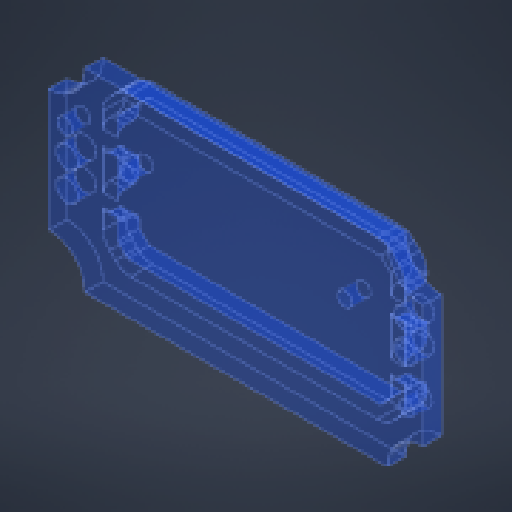
# Autodesk Inventor part: MID_PLATE
Saved by Autodesk Inventor 2024.3 (Build 283343000, 343)
## iProperties
Created: 2026-06-30
Part Number: MID_PLATE
Material: Generic
Document SubType Name: Modeling
Designer: REMOTE
Density: 1 g/cm^3
Appearance: Clear - Blue
Author: REMOTE
Autodesk Inventor part; units mm, degrees
ref_plane "YZ Plane" through (0, 0, 0) normal (1, 0, 0) x (0, 1, 0)
ref_plane "XZ Plane" through (0, 0, 0) normal (0, 1, 0) x (-1, 0, 0)
ref_plane "XY Plane" through (0, 0, 0) normal (0, 0, 1) x (1, 0, 0)
sketch "Sketch1" plane through (0, 0, 0) normal (0, 0, 1) x (1, 0, 0)
  line L0 (-71.4252, 28.7769) -> (-71.4252, -3.5231)
  line L1 (-71.4252, -3.5231) -> (-14.1252, -3.5231)
  line L2 (-14.1252, -3.5231) -> (-14.1252, 28.7769)
  line L3 (-14.1252, 28.7769) -> (-71.4252, 28.7769)
  line L4 (-16.6252, -1.0231) -> (-68.9252, -1.0231)
  line L5 (-68.9252, -1.0231) -> (-68.9252, 26.2769)
  line L6 (-68.9252, 26.2769) -> (-16.6252, 26.2769)
  line L7 (-16.6252, 26.2769) -> (-16.6252, -1.0231)
  line L8 (-16.6252, 0.2269) -> (-68.9252, 0.2269)
  line L9 (-68.9252, 25.0269) -> (-16.6252, 25.0269)
  line L10 (-68.7252, 26.0769) -> (-68.7252, -0.8231)
  line L11 (-68.7252, -0.8231) -> (-16.8252, -0.8231)
  line L12 (-16.8252, -0.8231) -> (-16.8252, 26.0769)
  line L13 (-16.8252, 26.0769) -> (-68.7252, 26.0769)
  point P0 (0, 0)
  point P1 (-42.7752, 12.6269)
  dimension "d0" = 0.2
  constraints: 28 end point, 3 other
  measures "d0" distance between parallel lines of L5 L10
extrude "Extrusion1" add sketch "Sketch1" along normal blind 2.5 contours L12 L11 L10 L8 | L8 L10 L9 L12 | L9 L10 L13 L12
sketch "Sketch2" plane through (0, 0, 0) normal (0, 0, -1) x (-1, 0, 0)
  line L0 (25.3752, 21.2419) -> (24.1752, 20.0419) projected
  line L1 (24.1752, 20.0419) -> (24.1752, 5.2119) projected
  line L2 (24.1752, 5.2119) -> (25.3752, 4.0119) projected
  line L3 (25.3752, 4.0119) -> (60.1752, 4.0119) projected
  line L4 (60.1752, 4.0119) -> (61.3752, 5.2119) projected
  line L5 (61.3752, 5.2119) -> (61.3752, 20.0419) projected
  line L6 (61.3752, 20.0419) -> (60.1752, 21.2419) projected
  line L7 (60.1752, 21.2419) -> (25.3752, 21.2419) projected
  circle A0 centre (57.8752, 16.3919) radius 1 projected
  circle A1 centre (27.6752, 8.9719) radius 1 projected
  circle A2 centre (57.8752, 8.9719) radius 1 projected
  circle A3 centre (27.6752, 16.3919) radius 1 projected
  line L8 (61.6752, 20.1662) -> (61.6752, 5.0876)
  line L9 (61.6752, 5.0876) -> (60.2994, 3.7119)
  line L10 (60.2994, 3.7119) -> (25.2509, 3.7119)
  line L11 (25.2509, 3.7119) -> (23.8752, 5.0876)
  line L12 (23.8752, 5.0876) -> (23.8752, 20.1662)
  line L13 (23.8752, 20.1662) -> (25.2509, 21.5419)
  line L14 (25.2509, 21.5419) -> (60.2994, 21.5419)
  line L15 (60.2994, 21.5419) -> (61.6752, 20.1662)
  line L16 (63.6752, 4.2592) -> (63.6752, 20.9946)
  line L17 (63.6752, 20.9946) -> (61.1279, 23.5419)
  line L18 (61.1279, 23.5419) -> (24.4225, 23.5419)
  line L19 (24.4225, 23.5419) -> (21.8752, 20.9946)
  line L20 (21.8752, 20.9946) -> (21.8752, 4.2592)
  line L21 (21.8752, 4.2592) -> (24.4225, 1.7119)
  line L22 (24.4225, 1.7119) -> (61.1279, 1.7119)
  line L23 (61.1279, 1.7119) -> (63.6752, 4.2592)
  point P0 (0, 0)
  dimension "d3" = 0.3
  dimension "d4" = 2
  constraints: 32 end point, 14 other
  measures "d3" distance between parallel lines of L5 L8
  measures "d4" distance between parallel lines of L8 L16
extrude "Extrusion2" add sketch "Sketch2" along normal blind 3 contours L23 L22 L21 L20 L19 L18 L17 L16
fillet "Fillet1" radius 3 8 edges at (-61.1279, 1.7119, -1.5) (-63.6752, 4.2592, -1.5) (-21.8752, 4.2592, -1.5) (-24.4225, 1.7119, -1.5) (-63.6752, 20.9946, -1.5) (-61.1279, 23.5419, -1.5) (-24.4225, 23.5419, -1.5) (-21.8752, 20.9946, -1.5)
sketch "Sketch3" plane through (0, 0, 0) normal (0, 0, -1) x (-1, 0, 0)
  circle A0 centre (27.6752, 16.3919) radius 1 projected
  circle A1 centre (57.8752, 16.3919) radius 1 projected
  point P0 (0, 0)
extrude "Extrusion3" cut sketch "Sketch3" against normal up to surface (2.5 mm away)
sketch "Sketch4" plane through (0, 0, 0) normal (0, 0, -1) x (-1, 0, 0)
  circle A0 centre (19.3252, 14.1769) radius 1.5
  circle A1 centre (66.2252, 14.1769) radius 1.5
  line L0 (68.7252, 26.0769) -> (68.7252, -0.8231) projected
  line L1 (16.8252, -0.8231) -> (16.8252, 26.0769) projected
  line L2 (68.7252, -0.8231) -> (16.8252, -0.8231) projected
  circle A2 centre (19.3252, 18.1769) radius 1.5
  circle A3 centre (66.2252, 10.1769) radius 1.5
  point P0 (0, 0)
  dimension "d10" = 3
  dimension "d11" = 3
  dimension "d12" = 2.5
  dimension "d13" = 2.5
  dimension "d14" = 15
  dimension "d15" = 15
  dimension "d28" = 3
  dimension "d29" = 4
  dimension "d30" = 3
  dimension "d31" = 4
  constraints: 4 centre point
  measures "d10" diameter of A0
  measures "d11" diameter of A1
  measures "d12" distance from line of L0 A1.centre
  measures "d13" distance from line of L1 A0.centre
  measures "d14" distance from line of L2 A0.centre
  measures "d15" distance from line of L2 A1.centre
  measures "d28" diameter of A2
  measures "d29" distance of A0.centre A2.centre
  measures "d30" diameter of A3
  measures "d31" distance of A3.centre A1.centre
extrude "Extrusion4" cut sketch "Sketch4" against normal up to surface (2.5 mm away)
sketch "Sketch5" plane through (0, 0, 0) normal (0, 0, -1) x (-1, 0, 0)
  circle A0 centre (19.1252, 7.5769) radius 0.95 projected
  circle A1 centre (66.5252, 17.7769) radius 0.95 projected
  circle A2 centre (19.1252, 7.5769) radius 1.05
  circle A3 centre (66.5252, 17.7769) radius 1.05
  point P0 (0, 0)
  dimension "d18" = 0.1
  dimension "d19" = 0.1
  constraints: 2 centre point
  measures "d18" radial gap between concentric circles of A0 A2
  measures "d19" radial gap between concentric circles of A1 A3
extrude "Extrusion5" cut sketch "Sketch5" against normal up to surface (2.5 mm away) contours A0 | A1 | A2 | A3
sketch "Sketch6" plane through (0, 0, 0) normal (0, 0, -1) x (-1, 0, 0)
  line L0 (68.7252, -0.8231) -> (16.8252, -0.8231) projected
  circle A0 centre (68.7252, -0.8231) radius 5
  line L1 (16.8252, 26.0769) -> (68.7252, 26.0769) projected
  circle A1 centre (68.7252, 26.0769) radius 5
  circle A2 centre (16.8252, 26.0769) radius 5
  line L2 (16.8252, -0.8231) -> (16.8252, 26.0769) projected
  circle A3 centre (16.8252, -0.8231) radius 5
  point P0 (0, 0)
  dimension "d22" = 10
  dimension "d23" = 10
  dimension "d24" = 10
  dimension "d25" = 10
  constraints: 4 centre point, 2 coincident
  measures "d22" diameter of A0
  measures "d23" diameter of A1
  measures "d24" diameter of A2
  measures "d25" diameter of A3
extrude "Extrusion6" cut sketch "Sketch6" against normal up to surface (2.5 mm away)
sketch "Sketch9" plane through (0, 0, 0) normal (0, 0, -1) x (-1, 0, 0)
  arc A0 (22.7538, 21.8733) -> (21.8752, 19.752) centre (24.8752, 19.752) ccw projected
  line L0 (21.8752, 19.752) -> (21.8752, 5.5019) projected
  arc A1 (21.8752, 5.5019) -> (22.7538, 3.3805) centre (24.8752, 5.5019) ccw projected
  line L1 (22.7538, 3.3805) -> (23.5438, 2.5906) projected
  arc A2 (23.5438, 2.5906) -> (25.6651, 1.7119) centre (25.6651, 4.7119) ccw projected
  line L2 (25.6651, 1.7119) -> (59.8852, 1.7119) projected
  arc A3 (59.8852, 1.7119) -> (62.0065, 2.5906) centre (59.8852, 4.7119) ccw projected
  line L3 (62.0065, 2.5906) -> (62.7965, 3.3805) projected
  arc A4 (62.7965, 3.3805) -> (63.6752, 5.5019) centre (60.6752, 5.5019) ccw projected
  line L4 (63.6752, 5.5019) -> (63.6752, 19.752) projected
  arc A5 (63.6752, 19.752) -> (62.7965, 21.8733) centre (60.6752, 19.752) ccw projected
  line L5 (62.7965, 21.8733) -> (62.0065, 22.6632) projected
  arc A6 (62.0065, 22.6632) -> (59.8852, 23.5419) centre (59.8852, 20.5419) ccw projected
  line L6 (59.8852, 23.5419) -> (25.6651, 23.5419) projected
  arc A7 (25.6651, 23.5419) -> (23.5438, 22.6632) centre (25.6651, 20.5419) ccw projected
  line L7 (23.5438, 22.6632) -> (22.7538, 21.8733) projected
  line L8 (61.6752, 20.1662) -> (61.6752, 5.0876) projected
  line L9 (61.6752, 5.0876) -> (60.2994, 3.7119) projected
  line L10 (60.2994, 3.7119) -> (25.2509, 3.7119) projected
  line L11 (25.2509, 3.7119) -> (23.8752, 5.0876) projected
  line L12 (23.8752, 5.0876) -> (23.8752, 20.1662) projected
  line L13 (23.8752, 20.1662) -> (25.2509, 21.5419) projected
  line L14 (25.2509, 21.5419) -> (60.2994, 21.5419) projected
  line L15 (60.2994, 21.5419) -> (61.6752, 20.1662) projected
  line L16 (63.6752, 19.752) -> (63.6752, 5.5019) projected
  line L17 (61.6752, 7.1194) -> (63.6752, 7.1194)
  line L18 (63.6752, 7.1194) -> (63.6752, 10.8782)
  line L19 (63.6752, 10.8782) -> (61.6752, 10.8782)
  line L20 (61.6752, 10.8782) -> (61.6752, 7.1194)
  line L21 (61.6752, 14.4111) -> (63.6752, 14.4111)
  line L22 (63.6752, 14.4111) -> (63.6752, 18.53)
  line L23 (63.6752, 18.53) -> (61.6752, 18.53)
  line L24 (61.6752, 18.53) -> (61.6752, 14.4111)
  line L25 (23.8752, 6.9317) -> (21.8752, 6.9317)
  line L26 (21.8752, 6.9317) -> (21.8752, 10.8782)
  line L27 (21.8752, 10.8782) -> (23.8752, 10.8782)
  line L28 (23.8752, 10.8782) -> (23.8752, 6.9317)
  line L29 (23.8752, 14.3506) -> (21.8752, 14.3506)
  line L30 (21.8752, 14.3506) -> (21.8752, 18.4702)
  line L31 (21.8752, 18.4702) -> (23.8752, 18.4702)
  line L32 (23.8752, 18.4702) -> (23.8752, 14.3506)
  point P0 (0, 0)
  constraints: 32 end point, 8 parallel, 8 point on line, 4 horizontal, 4 perpendicular
extrude "Extrusion7" cut sketch "Sketch9" along normal blind 3 contours L31 L12 L29 L0 | L27 L12 L25 L0 | L4 L21 L8 L23 | L4 L17 L8 L19
fillet "Fillet2" radius 1 16 edges at (-62.6752, 7.1194, 0) (-62.6752, 10.8782, 0) (-62.6752, 14.4111, 0) (-62.6752, 18.53, 0) (-62.6752, 14.4111, -3) (-62.6752, 10.8782, -3) (-62.6752, 7.1194, -3) (-62.6752, 18.53, -3) (-22.8752, 18.4702, 0) (-22.8752, 18.4702, -3) (-22.8752, 14.3506, 0) (-22.8752, 14.3506, -3) (-22.8752, 10.8782, -3) (-22.8752, 6.9317, -3) (-22.8752, 6.9317, 0) (-22.8752, 10.8782, 0)
body "Solid1"
